Autodesk Fusion 360 part; units mm, degrees
(part 2 of 8)
  spline S22 degree 5 poles (-2.980343, -5.720145) (-2.978626, -5.718892) (-2.975196, -5.716385) (-2.970061, -5.712616) (-2.963235, -5.707577) (-2.954738, -5.701255) (-2.946275, -5.694909) (-2.937848, -5.688539) (-2.929456, -5.682145) (-2.9211, -5.675727) (-2.912779, -5.669285) (-2.904494, -5.662819) (-2.896246, -5.656329) (-2.888035, -5.649814) (-2.87986, -5.643276) (-2.871723, -5.636713) (-2.863622, -5.630126) (-2.85556, -5.623515) (-2.847536, -5.616879) (-2.839549, -5.610219) (-2.831602, -5.603535) (-2.823693, -5.596825) (-2.815824, -5.590091) (-2.807994, -5.583333) (-2.800204, -5.576549) (-2.792454, -5.56974) (-2.784745, -5.562907) (-2.777076, -5.556048) (-2.769449, -5.549164) (-2.761864, -5.542255) (-2.754321, -5.53532) (-2.74682, -5.528359) (-2.739363, -5.521373) (-2.731949, -5.514361) (-2.72458, -5.507322) (-2.717254, -5.500258) (-2.709974, -5.493167) (-2.702738, -5.48605) (-2.695549, -5.478906) (-2.688406, -5.471736) (-2.681311, -5.464538) (-2.674264, -5.457312) (-2.667266, -5.450058) (-2.660318, -5.442777) (-2.653419, -5.435467) (-2.646572, -5.428129) (-2.639774, -5.420762) (-2.633028, -5.413368) (-2.626334, -5.405944) (-2.619694, -5.398491) (-2.613112, -5.391007) (-2.606588, -5.38349) (-2.600125, -5.37594) (-2.593724, -5.368358) (-2.587383, -5.360742) (-2.581101, -5.353096) (-2.574876, -5.34542) (-2.568709, -5.337713) (-2.562604, -5.329974) (-2.556569, -5.322198) (-2.550614, -5.314381) (-2.544748, -5.306517) (-2.540008, -5.300017) (-2.536467, -5.295076) (-2.534085, -5.291717) (-2.532839, -5.289949) (-2.532719, -5.289779) knots -1 -1 -1 -1 -1 -1 -0.98571429 -0.97142857 -0.95714286 -0.94285714 -0.92857143 -0.91428571 -0.9 -0.88571429 -0.87142857 -0.85714286 -0.84285714 -0.82857143 -0.81428571 -0.8 -0.78571429 -0.77142857 -0.75714286 -0.74285714 -0.72857143 -0.71428571 -0.7 -0.68571429 -0.67142857 -0.65714286 -0.64285714 -0.62857143 -0.61428571 -0.6 -0.58571429 -0.57142857 -0.55714286 -0.54285714 -0.52857143 -0.51428571 -0.5 -0.48571429 -0.47142857 -0.45714286 -0.44285714 -0.42857143 -0.41428571 -0.4 -0.38571429 -0.37142857 -0.35714286 -0.34285714 -0.32857143 -0.31428571 -0.3 -0.28571429 -0.27142857 -0.25714286 -0.24285714 -0.22857143 -0.21428571 -0.2 -0.18571429 -0.17142857 -0.15714286 -0.14285714 -0.12857143 -0.1270499 -0.1270499 -0.1270499 -0.1270499 -0.1270499 -0.1270499
  spline S23 degree 3 poles (-2.264018, -5.410236) (-2.259583, -5.391214) (-2.258906, -5.371507) (-2.265143, -5.332944) (-2.271998, -5.314456) (-2.292409, -5.281148) (-2.30577, -5.266646) (-2.337298, -5.243581) (-2.355164, -5.235238) (-2.393089, -5.225869) (-2.412785, -5.224934) (-2.451426, -5.230665) (-2.470003, -5.237276) (-2.495829, -5.25264) (-2.504278, -5.258953) (-2.519715, -5.273244) (-2.526661, -5.281181) (-2.532719, -5.289779) knots 0 0 0 0 0.00585967 0.00585967 0.01171933 0.01171933 0.017579 0.017579 0.02343867 0.02343867 0.02929834 0.02929834 0.035158 0.035158 0.03831344 0.03831344 0.04146887 0.04146887 0.04146887 0.04146887
  spline S24 degree 5 poles (-2.264018, -5.410236) (-2.264065, -5.410438) (-2.264556, -5.412545) (-2.26548, -5.416558) (-2.266812, -5.422489) (-2.268511, -5.430352) (-2.270479, -5.439964) (-2.272353, -5.44961) (-2.274143, -5.459289) (-2.275859, -5.468996) (-2.277509, -5.478727) (-2.279099, -5.488481) (-2.280627, -5.498259) (-2.282093, -5.508059) (-2.283495, -5.517883) (-2.284832, -5.527731) (-2.286103, -5.537602) (-2.287311, -5.547496) (-2.288458, -5.557412) (-2.289546, -5.567348) (-2.290578, -5.577304) (-2.291555, -5.58728) (-2.292477, -5.597274) (-2.293345, -5.607288) (-2.294158, -5.61732) (-2.294918, -5.62737) (-2.295623, -5.637438) (-2.296276, -5.647524) (-2.296877, -5.657628) (-2.297427, -5.667748) (-2.297927, -5.677885) (-2.298376, -5.688038) (-2.298776, -5.698207) (-2.299128, -5.708392) (-2.29943, -5.718592) (-2.299684, -5.728807) (-2.29989, -5.739038) (-2.300049, -5.749283) (-2.300161, -5.759543) (-2.300225, -5.769817) (-2.300244, -5.780105) (-2.300216, -5.790407) (-2.300143, -5.800722) (-2.300025, -5.811051) (-2.299861, -5.821394) (-2.299652, -5.831749) (-2.299399, -5.842117) (-2.299102, -5.852498) (-2.298761, -5.862891) (-2.298376, -5.873297) (-2.297947, -5.883714) (-2.297476, -5.894144) (-2.296961, -5.904585) (-2.296403, -5.915038) (-2.295803, -5.925503) (-2.295161, -5.935978) (-2.294476, -5.946465) (-2.293749, -5.956963) (-2.292981, -5.967472) (-2.292171, -5.977991) (-2.29132, -5.98852) (-2.290427, -5.99906) (-2.289494, -6.00961) (-2.288714, -6.018059) (-2.288111, -6.0244) (-2.287701, -6.028629) (-2.287494, -6.030744) knots 0.1270499 0.1270499 0.1270499 0.1270499 0.1270499 0.1270499 0.12857143 0.14285714 0.15714286 0.17142857 0.18571429 0.2 0.21428571 0.22857143 0.24285714 0.25714286 0.27142857 0.28571429 0.3 0.31428571 0.32857143 0.34285714 0.35714286 0.37142857 0.38571429 0.4 0.41428571 0.42857143 0.44285714 0.45714286 0.47142857 0.48571429 0.5 0.51428571 0.52857143 0.54285714 0.55714286 0.57142857 0.58571429 0.6 0.61428571 0.62857143 0.64285714 0.65714286 0.67142857 0.68571429 0.7 0.71428571 0.72857143 0.74285714 0.75714286 0.77142857 0.78571429 0.8 0.81428571 0.82857143 0.84285714 0.85714286 0.87142857 0.88571429 0.9 0.91428571 0.92857143 0.94285714 0.95714286 0.97142857 0.98571429 1 1 1 1 1 1
  arc A8 (-2.287494, -6.030744) -> (-2.072239, -6.108054) centre (0, 0) ccw
  spline S25 degree 5 poles (-2.072239, -6.108054) (-2.070733, -6.106554) (-2.067726, -6.103552) (-2.063226, -6.099044) (-2.057249, -6.093023) (-2.049817, -6.085477) (-2.042422, -6.077914) (-2.035066, -6.070332) (-2.027749, -6.062732) (-2.02047, -6.055113) (-2.01323, -6.047477) (-2.00603, -6.039822) (-1.998869, -6.032149) (-1.991748, -6.024457) (-1.984667, -6.016748) (-1.977627, -6.00902) (-1.970627, -6.001274) (-1.963669, -5.993509) (-1.956751, -5.985726) (-1.949875, -5.977925) (-1.943041, -5.970106) (-1.936249, -5.962268) (-1.9295, -5.954411) (-1.922793, -5.946537) (-1.91613, -5.938643) (-1.909511, -5.930731) (-1.902935, -5.922801) (-1.896403, -5.914852) (-1.889916, -5.906885) (-1.883475, -5.898898) (-1.877079, -5.890893) (-1.870729, -5.88287) (-1.864425, -5.874827) (-1.858169, -5.866765) (-1.85196, -5.858684) (-1.845799, -5.850584) (-1.839686, -5.842465) (-1.833622, -5.834327) (-1.827607, -5.82617) (-1.821642, -5.817992) (-1.815729, -5.809796) (-1.809868, -5.801579) (-1.804059, -5.793342) (-1.798304, -5.785085) (-1.792602, -5.776808) (-1.786955, -5.76851) (-1.781362, -5.760193) (-1.775823, -5.751855) (-1.770341, -5.743497) (-1.764917, -5.735117) (-1.759554, -5.726716) (-1.754254, -5.718292) (-1.74902, -5.709844) (-1.743851, -5.701373) (-1.738747, -5.692879) (-1.733705, -5.684363) (-1.728725, -5.675827) (-1.723807, -5.667269) (-1.718955, -5.658689) (-1.714178, -5.650083) (-1.709486, -5.641448) (-1.704889, -5.63278) (-1.701196, -5.625633) (-1.698451, -5.62021) (-1.69661, -5.616526) (-1.695649, -5.614589) (-1.695556, -5.614403) knots -1 -1 -1 -1 -1 -1 -0.98571429 -0.97142857 -0.95714286 -0.94285714 -0.92857143 -0.91428571 -0.9 -0.88571429 -0.87142857 -0.85714286 -0.84285714 -0.82857143 -0.81428571 -0.8 -0.78571429 -0.77142857 -0.75714286 -0.74285714 -0.72857143 -0.71428571 -0.7 -0.68571429 -0.67142857 -0.65714286 -0.64285714 -0.62857143 -0.61428571 -0.6 -0.58571429 -0.57142857 -0.55714286 -0.54285714 -0.52857143 -0.51428571 -0.5 -0.48571429 -0.47142857 -0.45714286 -0.44285714 -0.42857143 -0.41428571 -0.4 -0.38571429 -0.37142857 -0.35714286 -0.34285714 -0.32857143 -0.31428571 -0.3 -0.28571429 -0.27142857 -0.25714286 -0.24285714 -0.22857143 -0.21428571 -0.2 -0.18571429 -0.17142857 -0.15714286 -0.14285714 -0.12857143 -0.1270499 -0.1270499 -0.1270499 -0.1270499 -0.1270499 -0.1270499
  spline S26 degree 3 poles (-1.411616, -5.692431) (-1.410137, -5.672955) (-1.412476, -5.653376) (-1.424527, -5.616217) (-1.434124, -5.598992) (-1.45938, -5.56919) (-1.474798, -5.556898) (-1.509477, -5.538916) (-1.528408, -5.533397) (-1.567318, -5.529928) (-1.586925, -5.53201) (-1.62424, -5.543572) (-1.641589, -5.552942) (-1.664767, -5.572068) (-1.672153, -5.579597) (-1.685229, -5.596076) (-1.690881, -5.604981) (-1.695556, -5.614403) knots 0 0 0 0 0.00585967 0.00585967 0.01171933 0.01171933 0.017579 0.017579 0.02343867 0.02343867 0.02929834 0.02929834 0.035158 0.035158 0.03831344 0.03831344 0.04146887 0.04146887 0.04146887 0.04146887
  spline S27 degree 5 poles (-1.411616, -5.692431) (-1.411632, -5.692638) (-1.411795, -5.694795) (-1.412095, -5.698902) (-1.412507, -5.704967) (-1.412985, -5.712997) (-1.413463, -5.722796) (-1.413843, -5.732616) (-1.414134, -5.742455) (-1.414348, -5.75231) (-1.414494, -5.762179) (-1.414576, -5.772062) (-1.414594, -5.781958) (-1.414547, -5.791867) (-1.414433, -5.80179) (-1.41425, -5.811726) (-1.414, -5.821676) (-1.413683, -5.831638) (-1.413303, -5.841613) (-1.412862, -5.851599) (-1.412362, -5.861596) (-1.411804, -5.871604) (-1.41119, -5.881622) (-1.410519, -5.89165) (-1.409792, -5.901689) (-1.409008, -5.911737) (-1.408169, -5.921795) (-1.407274, -5.931863) (-1.406326, -5.94194) (-1.405325, -5.952025) (-1.404271, -5.962119) (-1.403165, -5.972222) (-1.402009, -5.982333) (-1.400801, -5.992452) (-1.399543, -6.002579) (-1.398235, -6.012713) (-1.396877, -6.022855) (-1.39547, -6.033005) (-1.394014, -6.043161) (-1.392509, -6.053325) (-1.390957, -6.063495) (-1.389357, -6.073672) (-1.38771, -6.083856) (-1.386016, -6.094045) (-1.384276, -6.104242) (-1.382489, -6.114444) (-1.380656, -6.124652) (-1.378778, -6.134865) (-1.376854, -6.145085) (-1.374885, -6.15531) (-1.372872, -6.16554) (-1.370813, -6.175775) (-1.368711, -6.186015) (-1.366564, -6.196261) (-1.364374, -6.206511) (-1.36214, -6.216766) (-1.359862, -6.227025) (-1.357541, -6.237289) (-1.355178, -6.247557) (-1.352772, -6.25783) (-1.350323, -6.268106) (-1.347832, -6.278386) (-1.345299, -6.28867) (-1.343239, -6.2969) (-1.341675, -6.303075) (-1.340624, -6.307192) (-1.340096, -6.30925) knots 0.1270499 0.1270499 0.1270499 0.1270499 0.1270499 0.1270499 0.12857143 0.14285714 0.15714286 0.17142857 0.18571429 0.2 0.21428571 0.22857143 0.24285714 0.25714286 0.27142857 0.28571429 0.3 0.31428571 0.32857143 0.34285714 0.35714286 0.37142857 0.38571429 0.4 0.41428571 0.42857143 0.44285714 0.45714286 0.47142857 0.48571429 0.5 0.51428571 0.52857143 0.54285714 0.55714286 0.57142857 0.58571429 0.6 0.61428571 0.62857143 0.64285714 0.65714286 0.67142857 0.68571429 0.7 0.71428571 0.72857143 0.74285714 0.75714286 0.77142857 0.78571429 0.8 0.81428571 0.82857143 0.84285714 0.85714286 0.87142857 0.88571429 0.9 0.91428571 0.92857143 0.94285714 0.95714286 0.97142857 0.98571429 1 1 1 1 1 1
  arc A9 (-1.340096, -6.30925) -> (-1.115563, -6.352796) centre (0, 0) ccw
  spline S28 degree 5 poles (-1.115563, -6.352796) (-1.114304, -6.351084) (-1.11179, -6.347658) (-1.108031, -6.342516) (-1.103044, -6.335653) (-1.09685, -6.327061) (-1.090697, -6.318457) (-1.084584, -6.309841) (-1.078513, -6.301213) (-1.072482, -6.292573) (-1.066493, -6.283921) (-1.060545, -6.275257) (-1.05464, -6.26658) (-1.048776, -6.257892) (-1.042956, -6.249192) (-1.037177, -6.24048) (-1.031442, -6.231756) (-1.02575, -6.22302) (-1.020102, -6.214273) (-1.014497, -6.205513) (-1.008937, -6.196742) (-1.003421, -6.187959) (-0.99795, -6.179165) (-0.992525, -6.170359) (-0.987144, -6.161541) (-0.98181, -6.152711) (-0.976522, -6.14387) (-0.97128, -6.135017) (-0.966086, -6.126153) (-0.960939, -6.117277) (-0.95584, -6.108389) (-0.950789, -6.09949) (-0.945787, -6.090579) (-0.940835, -6.081657) (-0.935932, -6.072723) (-0.931079, -6.063778) (-0.926277, -6.054821) (-0.921527, -6.045852) (-0.916828, -6.036872) (-0.912181, -6.02788) (-0.907588, -6.018877) (-0.90305, -6.009862) (-0.898567, -6.000835) (-0.894139, -5.991796) (-0.889768, -5.982746) (-0.885454, -5.973683) (-0.881195, -5.964609) (-0.876995, -5.955524) (-0.872852, -5.946427) (-0.868771, -5.937318) (-0.864753, -5.928196) (-0.860802, -5.919061) (-0.856918, -5.909913) (-0.853103, -5.900753) (-0.849355, -5.891579) (-0.845673, -5.882394) (-0.842054, -5.873197) (-0.8385, -5.863989) (-0.835015, -5.854768) (-0.831607, -5.845534) (-0.828288, -5.836284) (-0.825068, -5.827017) (-0.82251, -5.81939) (-0.820625, -5.813611) (-0.819368, -5.809689) (-0.818713, -5.807628) (-0.81865, -5.80743) knots -1 -1 -1 -1 -1 -1 -0.98571429 -0.97142857 -0.95714286 -0.94285714 -0.92857143 -0.91428571 -0.9 -0.88571429 -0.87142857 -0.85714286 -0.84285714 -0.82857143 -0.81428571 -0.8 -0.78571429 -0.77142857 -0.75714286 -0.74285714 -0.72857143 -0.71428571 -0.7 -0.68571429 -0.67142857 -0.65714286 -0.64285714 -0.62857143 -0.61428571 -0.6 -0.58571429 -0.57142857 -0.55714286 -0.54285714 -0.52857143 -0.51428571 -0.5 -0.48571429 -0.47142857 -0.45714286 -0.44285714 -0.42857143 -0.41428571 -0.4 -0.38571429 -0.37142857 -0.35714286 -0.34285714 -0.32857143 -0.31428571 -0.3 -0.28571429 -0.27142857 -0.25714286 -0.24285714 -0.22857143 -0.21428571 -0.2 -0.18571429 -0.17142857 -0.15714286 -0.14285714 -0.12857143 -0.1270499 -0.1270499 -0.1270499 -0.1270499 -0.1270499 -0.1270499
  spline S29 degree 3 poles (-0.526127, -5.8412) (-0.527638, -5.821726) (-0.532938, -5.802734) (-0.55052, -5.76785) (-0.562634, -5.752292) (-0.592144, -5.726694) (-0.609257, -5.7169) (-0.646275, -5.704423) (-0.665826, -5.701859) (-0.70481, -5.704369) (-0.72387, -5.70942) (-0.758982, -5.726543) (-0.774698, -5.738451) (-0.794685, -5.760891) (-0.800835, -5.769459) (-0.811241, -5.787741) (-0.815469, -5.797404) (-0.81865, -5.80743) knots 0 0 0 0 0.00585967 0.00585967 0.01171933 0.01171933 0.017579 0.017579 0.02343867 0.02343867 0.02929834 0.02929834 0.035158 0.035158 0.03831344 0.03831344 0.04146887 0.04146887 0.04146887 0.04146887
  spline S30 degree 5 poles (-0.526127, -5.8412) (-0.526111, -5.841408) (-0.525943, -5.843564) (-0.525613, -5.847669) (-0.525094, -5.853725) (-0.524341, -5.861734) (-0.523317, -5.871492) (-0.522193, -5.881255) (-0.52098, -5.891022) (-0.519687, -5.900794) (-0.518325, -5.91057) (-0.516897, -5.920349) (-0.515404, -5.930132) (-0.513845, -5.939918) (-0.512217, -5.949708) (-0.51052, -5.9595) (-0.508754, -5.969294) (-0.50692, -5.979092) (-0.505022, -5.988891) (-0.503061, -5.998693) (-0.501041, -6.008496) (-0.498963, -6.018302) (-0.496826, -6.028109) (-0.494632, -6.037917) (-0.492381, -6.047727) (-0.490073, -6.057538) (-0.487708, -6.06735) (-0.485287, -6.077163) (-0.482812, -6.086977) (-0.480282, -6.096792) (-0.4777, -6.106607) (-0.475065, -6.116422) (-0.472379, -6.126238) (-0.469641, -6.136054) (-0.466851, -6.14587) (-0.464012, -6.155686) (-0.461121, -6.165502) (-0.458181, -6.175318) (-0.455192, -6.185133) (-0.452154, -6.194948) (-0.449067, -6.204762) (-0.445933, -6.214576) (-0.442751, -6.224388) (-0.439521, -6.2342) (-0.436245, -6.244011) (-0.432922, -6.253821) (-0.429552, -6.26363) (-0.426137, -6.273437) (-0.422675, -6.283243) (-0.419169, -6.293047) (-0.415617, -6.30285) (-0.41202, -6.312651) (-0.408379, -6.322451) (-0.404694, -6.332248) (-0.400964, -6.342044) (-0.397191, -6.351838) (-0.393374, -6.361629) (-0.389514, -6.371419) (-0.385611, -6.381206) (-0.381665, -6.39099) (-0.377676, -6.400772) (-0.373645, -6.410552) (-0.369572, -6.420328) (-0.36628, -6.428148) (-0.363791, -6.434011) (-0.362124, -6.437919) (-0.361288, -6.439873) knots 0.1270499 0.1270499 0.1270499 0.1270499 0.1270499 0.1270499 0.12857143 0.14285714 0.15714286 0.17142857 0.18571429 0.2 0.21428571 0.22857143 0.24285714 0.25714286 0.27142857 0.28571429 0.3 0.31428571 0.32857143 0.34285714 0.35714286 0.37142857 0.38571429 0.4 0.41428571 0.42857143 0.44285714 0.45714286 0.47142857 0.48571429 0.5 0.51428571 0.52857143 0.54285714 0.55714286 0.57142857 0.58571429 0.6 0.61428571 0.62857143 0.64285714 0.65714286 0.67142857 0.68571429 0.7 0.71428571 0.72857143 0.74285714 0.75714286 0.77142857 0.78571429 0.8 0.81428571 0.82857143 0.84285714 0.85714286 0.87142857 0.88571429 0.9 0.91428571 0.92857143 0.94285714 0.95714286 0.97142857 0.98571429 1 1 1 1 1 1
  arc A10 (-0.361288, -6.439873) -> (-0.132739, -6.448634) centre (0, 0) ccw
  spline S31 degree 5 poles (-0.132739, -6.448634) (-0.131756, -6.44675) (-0.129795, -6.44298) (-0.126865, -6.437325) (-0.122984, -6.42978) (-0.118174, -6.420344) (-0.113406, -6.410902) (-0.108681, -6.401454) (-0.103997, -6.392) (-0.099356, -6.382541) (-0.094758, -6.373075) (-0.090203, -6.363605) (-0.085691, -6.354129) (-0.081223, -6.344647) (-0.076798, -6.33516) (-0.072417, -6.325669) (-0.068081, -6.316171) (-0.063789, -6.306669) (-0.059542, -6.297162) (-0.055341, -6.28765) (-0.051185, -6.278133) (-0.047074, -6.268611) (-0.04301, -6.259084) (-0.038992, -6.249553) (-0.035021, -6.240017) (-0.031097, -6.230477) (-0.02722, -6.220932) (-0.023391, -6.211383) (-0.019611, -6.201829) (-0.015879, -6.192272) (-0.012196, -6.18271) (-0.008563, -6.173144) (-0.00498, -6.163574) (-0.001448, -6.154) (0.002034, -6.144423) (0.005464, -6.134841) (0.008842, -6.125256) (0.012168, -6.115668) (0.015441, -6.106076) (0.018661, -6.09648) (0.021826, -6.086881) (0.024935, -6.077279) (0.027987, -6.067673) (0.030983, -6.058065) (0.033921, -6.048453) (0.036802, -6.038838) (0.039625, -6.029221) (0.04239, -6.0196) (0.045095, -6.009978) (0.047738, -6.000352) (0.050316, -5.990724) (0.052827, -5.981093) (0.055269, -5.97146) (0.057641, -5.961824) (0.059944, -5.952186) (0.062182, -5.942546) (0.064354, -5.932905) (0.066461, -5.923262) (0.068498, -5.913617) (0.070456, -5.903971) (0.072323, -5.894323) (0.074091, -5.884673) (0.075455, -5.876745) (0.076436, -5.870746) (0.07708, -5.866678) (0.077412, -5.864541) (0.077444, -5.864336) knots -1 -1 -1 -1 -1 -1 -0.98571429 -0.97142857 -0.95714286 -0.94285714 -0.92857143 -0.91428571 -0.9 -0.88571429 -0.87142857 -0.85714286 -0.84285714 -0.82857143 -0.81428571 -0.8 -0.78571429 -0.77142857 -0.75714286 -0.74285714 -0.72857143 -0.71428571 -0.7 -0.68571429 -0.67142857 -0.65714286 -0.64285714 -0.62857143 -0.61428571 -0.6 -0.58571429 -0.57142857 -0.55714286 -0.54285714 -0.52857143 -0.51428571 -0.5 -0.48571429 -0.47142857 -0.45714286 -0.44285714 -0.42857143 -0.41428571 -0.4 -0.38571429 -0.37142857 -0.35714286 -0.34285714 -0.32857143 -0.31428571 -0.3 -0.28571429 -0.27142857 -0.25714286 -0.24285714 -0.22857143 -0.21428571 -0.2 -0.18571429 -0.17142857 -0.15714286 -0.14285714 -0.12857143 -0.1270499 -0.1270499 -0.1270499 -0.1270499 -0.1270499 -0.1270499
  spline S32 degree 3 poles (0.371694, -5.853057) (0.367228, -5.834042) (0.359091, -5.816081) (0.33639, -5.78429) (0.322043, -5.770763) (0.288972, -5.74997) (0.270564, -5.742903) (0.232075, -5.736223) (0.212362, -5.736673) (0.174218, -5.745105) (0.156152, -5.753006) (0.124066, -5.775288) (0.110352, -5.789456) (0.094025, -5.814684) (0.089254, -5.824091) (0.081761, -5.843747) (0.079058, -5.853942) (0.077444, -5.864336) knots 0 0 0 0 0.00585967 0.00585967 0.01171933 0.01171933 0.017579 0.017579 0.02343867 0.02343867 0.02929834 0.02929834 0.035158 0.035158 0.03831344 0.03831344 0.04146887 0.04146887 0.04146887 0.04146887
  spline S33 degree 5 poles (0.371694, -5.853057) (0.371741, -5.853259) (0.372236, -5.855364) (0.373189, -5.859371) (0.374627, -5.865277) (0.376594, -5.873077) (0.379095, -5.882565) (0.381696, -5.892041) (0.384386, -5.901509) (0.387156, -5.910969) (0.389994, -5.920422) (0.392898, -5.929869) (0.395867, -5.93931) (0.398902, -5.948743) (0.402004, -5.958169) (0.405176, -5.967587) (0.408417, -5.976998) (0.411725, -5.9864) (0.415097, -5.995795) (0.41853, -6.005183) (0.422023, -6.014563) (0.425574, -6.023936) (0.429183, -6.033302) (0.432848, -6.042661) (0.436571, -6.052012) (0.44035, -6.061356) (0.444185, -6.070692) (0.448075, -6.08002) (0.452019, -6.089341) (0.456017, -6.098655) (0.460068, -6.107961) (0.46417, -6.117259) (0.468323, -6.126549) (0.472528, -6.135832) (0.476783, -6.145108) (0.481088, -6.154375) (0.485442, -6.163635) (0.489846, -6.172887) (0.494299, -6.182131) (0.498799, -6.191367) (0.503348, -6.200595) (0.507944, -6.209815) (0.512587, -6.219027) (0.517276, -6.228231) (0.522012, -6.237426) (0.526793, -6.246614) (0.531621, -6.255793) (0.536493, -6.264964) (0.541411, -6.274127) (0.546373, -6.283281) (0.551379, -6.292427) (0.55643, -6.301564) (0.561524, -6.310693) (0.566662, -6.319813) (0.571843, -6.328925) (0.577067, -6.338028) (0.582334, -6.347122) (0.587643, -6.356207) (0.592995, -6.365284) (0.598388, -6.374351) (0.603823, -6.38341) (0.6093, -6.392459) (0.614818, -6.4015) (0.619265, -6.408725) (0.622619, -6.41414) (0.624864, -6.417748) (0.625988, -6.419551) knots 0.1270499 0.1270499 0.1270499 0.1270499 0.1270499 0.1270499 0.12857143 0.14285714 0.15714286 0.17142857 0.18571429 0.2 0.21428571 0.22857143 0.24285714 0.25714286 0.27142857 0.28571429 0.3 0.31428571 0.32857143 0.34285714 0.35714286 0.37142857 0.38571429 0.4 0.41428571 0.42857143 0.44285714 0.45714286 0.47142857 0.48571429 0.5 0.51428571 0.52857143 0.54285714 0.55714286 0.57142857 0.58571429 0.6 0.61428571 0.62857143 0.64285714 0.65714286 0.67142857 0.68571429 0.7 0.71428571 0.72857143 0.74285714 0.75714286 0.77142857 0.78571429 0.8 0.81428571 0.82857143 0.84285714 0.85714286 0.87142857 0.88571429 0.9 0.91428571 0.92857143 0.94285714 0.95714286 0.97142857 0.98571429 1 1 1 1 1 1
  arc A11 (0.625988, -6.419551) -> (0.853196, -6.393321) centre (0, 0) ccw
  spline S34 degree 5 poles (0.853196, -6.393321) (0.85388, -6.391309) (0.855243, -6.387284) (0.857275, -6.381248) (0.859959, -6.373199) (0.863272, -6.363139) (0.866542, -6.35308) (0.86977, -6.343022) (0.872956, -6.332964) (0.876098, -6.322907) (0.879198, -6.31285) (0.882254, -6.302795) (0.885267, -6.292742) (0.888235, -6.282689) (0.89116, -6.272638) (0.89404, -6.262589) (0.896876, -6.252541) (0.899667, -6.242495) (0.902413, -6.232451) (0.905113, -6.222409) (0.907768, -6.212369) (0.910377, -6.202331) (0.912939, -6.192296) (0.915455, -6.182263) (0.917924, -6.172233) (0.920346, -6.162205) (0.92272, -6.15218) (0.925046, -6.142159) (0.927324, -6.13214) (0.929553, -6.122125) (0.931733, -6.112113) (0.933863, -6.102105) (0.935943, -6.0921) (0.937973, -6.082099) (0.939952, -6.072102) (0.941879, -6.06211) (0.943755, -6.052121) (0.945578, -6.042137) (0.947349, -6.032158) (0.949065, -6.022183) (0.950728, -6.012214) (0.952335, -6.002249) (0.953885, -5.99229) (0.955379, -5.982337) (0.956816, -5.972389) (0.958195, -5.962448) (0.959517, -5.952512) (0.960781, -5.942582) (0.961985, -5.932659) (0.963128, -5.922743) (0.964206, -5.912834) (0.965217, -5.902933) (0.96616, -5.89304) (0.967033, -5.883155) (0.967839, -5.873278) (0.968578, -5.86341) (0.969253, -5.85355) (0.969863, -5.843698) (0.970404, -5.833856) (0.970867, -5.824024) (0.97124, -5.814204) (0.971514, -5.804397) (0.971652, -5.796353) (0.971705, -5.790275) (0.97172, -5.786157) (0.971723, -5.783994) (0.971723, -5.783786) knots -1 -1 -1 -1 -1 -1 -0.98571429 -0.97142857 -0.95714286 -0.94285714 -0.92857143 -0.91428571 -0.9 -0.88571429 -0.87142857 -0.85714286 -0.84285714 -0.82857143 -0.81428571 -0.8 -0.78571429 -0.77142857 -0.75714286 -0.74285714 -0.72857143 -0.71428571 -0.7 -0.68571429 -0.67142857 -0.65714286 -0.64285714 -0.62857143 -0.61428571 -0.6 -0.58571429 -0.57142857 -0.55714286 -0.54285714 -0.52857143 -0.51428571 -0.5 -0.48571429 -0.47142857 -0.45714286 -0.44285714 -0.42857143 -0.41428571 -0.4 -0.38571429 -0.37142857 -0.35714286 -0.34285714 -0.32857143 -0.31428571 -0.3 -0.28571429 -0.27142857 -0.25714286 -0.24285714 -0.22857143 -0.21428571 -0.2 -0.18571429 -0.17142857 -0.15714286 -0.14285714 -0.12857143 -0.1270499 -0.1270499 -0.1270499 -0.1270499 -0.1270499 -0.1270499
  spline S35 degree 3 poles (1.260803, -5.727723) (1.253486, -5.709612) (1.242703, -5.693104) (1.215415, -5.665151) (1.199171, -5.653973) (1.163314, -5.638472) (1.144043, -5.634297) (1.104985, -5.633571) (1.085572, -5.637025) (1.049163, -5.651181) (1.032514, -5.661747) (1.004205, -5.688666) (0.992815, -5.704761) (0.98053, -5.732186) (0.977252, -5.74221) (0.972846, -5.76278) (0.971731, -5.773268) (0.971723, -5.783786) knots 0 0 0 0 0.00585967 0.00585967 0.01171933 0.01171933 0.017579 0.017579 0.02343867 0.02343867 0.02929834 0.02929834 0.035158 0.035158 0.03831344 0.03831344 0.04146887 0.04146887 0.04146887 0.04146887
  spline S36 degree 5 poles (1.260803, -5.727723) (1.260881, -5.727916) (1.261691, -5.72992) (1.263245, -5.733735) (1.265567, -5.739352) (1.268701, -5.746761) (1.272621, -5.755755) (1.276638, -5.764724) (1.280743, -5.77367) (1.284924, -5.782596) (1.289172, -5.791505) (1.293484, -5.800398) (1.297859, -5.809275) (1.302298, -5.818134) (1.306803, -5.826976) (1.311376, -5.8358) (1.316015, -5.844605) (1.320719, -5.853393) (1.325486, -5.862163) (1.330312, -5.870916) (1.335196, -5.879653) (1.340136, -5.888375) (1.345132, -5.89708) (1.350183, -5.905769) (1.35529, -5.914443) (1.360451, -5.9231) (1.365666, -5.931741) (1.370934, -5.940367) (1.376255, -5.948976) (1.381628, -5.95757) (1.387052, -5.966149) (1.392525, -5.974712) (1.398048, -5.98326) (1.40362, -5.991792) (1.409241, -6.000309) (1.41491, -6.008811) (1.420628, -6.017297) (1.426392, -6.025768) (1.432203, -6.034224) (1.438061, -6.042665) (1.443965, -6.051091) (1.449915, -6.059501) (1.455909, -6.067896) (1.461949, -6.076277) (1.468033, -6.084642) (1.474161, -6.092992) (1.480333, -6.101326) (1.486548, -6.109646) (1.492807, -6.117951) (1.499108, -6.12624) (1.505452, -6.134515) (1.511838, -6.142774) (1.518266, -6.151018) (1.524736, -6.159247) (1.531247, -6.167461) (1.5378, -6.17566) (1.544393, -6.183843) (1.551027, -6.192012) (1.557701, -6.200165) (1.564416, -6.208303) (1.57117, -6.216426) (1.577963, -6.224533) (1.584797, -6.232625) (1.590295, -6.239087) (1.594436, -6.243926) (1.597205, -6.247149) (1.598591, -6.24876) knots 0.1270499 0.1270499 0.1270499 0.1270499 0.1270499 0.1270499 0.12857143 0.14285714 0.15714286 0.17142857 0.18571429 0.2 0.21428571 0.22857143 0.24285714 0.25714286 0.27142857 0.28571429 0.3 0.31428571 0.32857143 0.34285714 0.35714286 0.37142857 0.38571429 0.4 0.41428571 0.42857143 0.44285714 0.45714286 0.47142857 0.48571429 0.5 0.51428571 0.52857143 0.54285714 0.55714286 0.57142857 0.58571429 0.6 0.61428571 0.62857143 0.64285714 0.65714286 0.67142857 0.68571429 0.7 0.71428571 0.72857143 0.74285714 0.75714286 0.77142857 0.78571429 0.8 0.81428571 0.82857143 0.84285714 0.85714286 0.87142857 0.88571429 0.9 0.91428571 0.92857143 0.94285714 0.95714286 0.97142857 0.98571429 1 1 1 1 1 1
  arc A12 (1.598591, -6.24876) -> (1.819133, -6.188155) centre (0, 0) ccw
  spline S37 degree 5 poles (1.819133, -6.188155) (1.819501, -6.186061) (1.820234, -6.181876) (1.821321, -6.1756) (1.822745, -6.167236) (1.824483, -6.156788) (1.82618, -6.146348) (1.827835, -6.135914) (1.829447, -6.125488) (1.831018, -6.115069) (1.832546, -6.104658) (1.834032, -6.094254) (1.835474, -6.083858) (1.836874, -6.07347) (1.83823, -6.063091) (1.839542, -6.052719) (1.840811, -6.042356) (1.842035, -6.032002) (1.843216, -6.021657) (1.844352, -6.01132) (1.845443, -6.000992) (1.846489, -5.990674) (1.847489, -5.980365) (1.848444, -5.970066) (1.849353, -5.959776) (1.850216, -5.949496) (1.851032, -5.939227) (1.851801, -5.928968) (1.852523, -5.918719) (1.853197, -5.90848) (1.853823, -5.898253) (1.854401, -5.888037) (1.854929, -5.877832) (1.855408, -5.867639) (1.855838, -5.857457) (1.856217, -5.847287) (1.856546, -5.837129) (1.856824, -5.826984) (1.857051, -5.816851) (1.857225, -5.806732) (1.857346, -5.796625) (1.857413, -5.786532) (1.857425, -5.776453) (1.857382, -5.766389) (1.857283, -5.756338) (1.857129, -5.746303) (1.856919, -5.736281) (1.856652, -5.726275) (1.856327, -5.716285) (1.855943, -5.706311) (1.855496, -5.696353) (1.854984, -5.686414) (1.854405, -5.676493) (1.853759, -5.66659) (1.853048, -5.656706) (1.852272, -5.64684) (1.851434, -5.636993) (1.850533, -5.627164) (1.849566, -5.617354) (1.848522, -5.607567) (1.847392, -5.597805) (1.846165, -5.588071) (1.845073, -5.580101) (1.844199, -5.574086) (1.843585, -5.570013) (1.843257, -5.567876) (1.843226, -5.56767) knots -1 -1 -1 -1 -1 -1 -0.98571429 -0.97142857 -0.95714286 -0.94285714 -0.92857143 -0.91428571 -0.9 -0.88571429 -0.87142857 -0.85714286 -0.84285714 -0.82857143 -0.81428571 -0.8 -0.78571429 -0.77142857 -0.75714286 -0.74285714 -0.72857143 -0.71428571 -0.7 -0.68571429 -0.67142857 -0.65714286 -0.64285714 -0.62857143 -0.61428571 -0.6 -0.58571429 -0.57142857 -0.55714286 -0.54285714 -0.52857143 -0.51428571 -0.5 -0.48571429 -0.47142857 -0.45714286 -0.44285714 -0.42857143 -0.41428571 -0.4 -0.38571429 -0.37142857 -0.35714286 -0.34285714 -0.32857143 -0.31428571 -0.3 -0.28571429 -0.27142857 -0.25714286 -0.24285714 -0.22857143 -0.21428571 -0.2 -0.18571429 -0.17142857 -0.15714286 -0.14285714 -0.12857143 -0.1270499 -0.1270499 -0.1270499 -0.1270499 -0.1270499 -0.1270499
  spline S38 degree 3 poles (2.120359, -5.468135) (2.110364, -5.451354) (2.097187, -5.436686) (2.065952, -5.413225) (2.048193, -5.404658) (2.010389, -5.394812) (1.990707, -5.393629) (1.951996, -5.398872) (1.933337, -5.40525) (1.899516, -5.424797) (1.884675, -5.437781) (1.860807, -5.468706) (1.852007, -5.486351) (1.844053, -5.51533) (1.842343, -5.525737) (1.841129, -5.546738) (1.841628, -5.557274) (1.843226, -5.56767) knots 0 0 0 0 0.00585967 0.00585967 0.01171933 0.01171933 0.017579 0.017579 0.02343867 0.02343867 0.02929834 0.02929834 0.035158 0.035158 0.03831344 0.03831344 0.04146887 0.04146887 0.04146887 0.04146887
  spline S39 degree 5 poles (2.120359, -5.468135) (2.120466, -5.468314) (2.121573, -5.470172) (2.12369, -5.473704) (2.126843, -5.478901) (2.131072, -5.485745) (2.136318, -5.494035) (2.141658, -5.502286) (2.147079, -5.5105) (2.152574, -5.518684) (2.158133, -5.52684) (2.163752, -5.534971) (2.16943, -5.543075) (2.17517, -5.551153) (2.180972, -5.559204) (2.186838, -5.567226) (2.192767, -5.57522) (2.198757, -5.583186) (2.204807, -5.591126) (2.210913, -5.59904) (2.217073, -5.606929) (2.223287, -5.614794) (2.229553, -5.622635) (2.235871, -5.630452) (2.242242, -5.638244) (2.248664, -5.646012) (2.255137, -5.653756) (2.26166, -5.661476) (2.268233, -5.669172) (2.274855, -5.676846) (2.281524, -5.684496) (2.288241, -5.692123) (2.295004, -5.699727) (2.301813, -5.707309) (2.308668, -5.714868) (2.315569, -5.722405) (2.322515, -5.729919) (2.329505, -5.737411) (2.336539, -5.744881) (2.343616, -5.752329) (2.350737, -5.759754) (2.357901, -5.767158) (2.365107, -5.77454) (2.372355, -5.7819) (2.379644, -5.789238) (2.386975, -5.796555) (2.394347, -5.80385) (2.40176, -5.811123) (2.409212, -5.818375) (2.416705, -5.825606) (2.424238, -5.832815) (2.43181, -5.840002) (2.439421, -5.847169) (2.447072, -5.854314) (2.45476, -5.861437) (2.462488, -5.86854) (2.470253, -5.875621) (2.478056, -5.882681) (2.485896, -5.88972) (2.493774, -5.896737) (2.501689, -5.903734) (2.509641, -5.910709) (2.517629, -5.917664) (2.52405, -5.92321) (2.528881, -5.927361) (2.532109, -5.930123) (2.533725, -5.931504) knots 0.1270499 0.1270499 0.1270499 0.1270499 0.1270499 0.1270499 0.12857143 0.14285714 0.15714286 0.17142857 0.18571429 0.2 0.21428571 0.22857143 0.24285714 0.25714286 0.27142857 0.28571429 0.3 0.31428571 0.32857143 0.34285714 0.35714286 0.37142857 0.38571429 0.4 0.41428571 0.42857143 0.44285714 0.45714286 0.47142857 0.48571429 0.5 0.51428571 0.52857143 0.54285714 0.55714286 0.57142857 0.58571429 0.6 0.61428571 0.62857143 0.64285714 0.65714286 0.67142857 0.68571429 0.7 0.71428571 0.72857143 0.74285714 0.75714286 0.77142857 0.78571429 0.8 0.81428571 0.82857143 0.84285714 0.85714286 0.87142857 0.88571429 0.9 0.91428571 0.92857143 0.94285714 0.95714286 0.97142857 0.98571429 1 1 1 1 1 1
  arc A13 (2.533725, -5.931504) -> (2.742431, -5.837943) centre (0, 0) ccw
  spline S40 degree 5 poles (2.742431, -5.837943) (2.742475, -5.835818) (2.742561, -5.83157) (2.742677, -5.825201) (2.742807, -5.816718) (2.74293, -5.806127) (2.743013, -5.79555) (2.743056, -5.784986) (2.743058, -5.774436) (2.74302, -5.763899) (2.742941, -5.753377) (2.742821, -5.742868) (2.74266, -5.732374) (2.742457, -5.721894) (2.742213, -5.711429) (2.741927, -5.700979) (2.741599, -5.690544) (2.741228, -5.680124) (2.740816, -5.66972) (2.74036, -5.659331) (2.739862, -5.648958) (2.739321, -5.638601) (2.738736, -5.62826) (2.738107, -5.617935) (2.737435, -5.607628) (2.736718, -5.597337) (2.735957, -5.587063) (2.735151, -5.576806) (2.7343, -5.566567) (2.733404, -5.556346) (2.732461, -5.546143) (2.731472, -5.535959) (2.730437, -5.525793) (2.729355, -5.515646) (2.728225, -5.505518) (2.727047, -5.495409) (2.725822, -5.48532) (2.724548, -5.475251) (2.723225, -5.465203) (2.721852, -5.455175) (2.720429, -5.445169) (2.718955, -5.435184) (2.717428, -5.425221) (2.715849, -5.415281) (2.714218, -5.405364) (2.712533, -5.395469) (2.710796, -5.385597) (2.709004, -5.375749) (2.707159, -5.365925) (2.705256, -5.356127) (2.703294, -5.346354) (2.701271, -5.336609) (2.699185, -5.326893) (2.697035, -5.317205) (2.694823, -5.307546) (2.69255, -5.297914) (2.690219, -5.28831) (2.687828, -5.278733) (2.685375, -5.269187) (2.682849, -5.259673) (2.680242, -5.250198) (2.677544, -5.240765) (2.675248, -5.233055) (2.673466, -5.227244) (2.672237, -5.223313) (2.671587, -5.221251) (2.671525, -5.221052) knots -1 -1 -1 -1 -1 -1 -0.98571429 -0.97142857 -0.95714286 -0.94285714 -0.92857143 -0.91428571 -0.9 -0.88571429 -0.87142857 -0.85714286 -0.84285714 -0.82857143 -0.81428571 -0.8 -0.78571429 -0.77142857 -0.75714286 -0.74285714 -0.72857143 -0.71428571 -0.7 -0.68571429 -0.67142857 -0.65714286 -0.64285714 -0.62857143 -0.61428571 -0.6 -0.58571429 -0.57142857 -0.55714286 -0.54285714 -0.52857143 -0.51428571 -0.5 -0.48571429 -0.47142857 -0.45714286 -0.44285714 -0.42857143 -0.41428571 -0.4 -0.38571429 -0.37142857 -0.35714286 -0.34285714 -0.32857143 -0.31428571 -0.3 -0.28571429 -0.27142857 -0.25714286 -0.24285714 -0.22857143 -0.21428571 -0.2 -0.18571429 -0.17142857 -0.15714286 -0.14285714 -0.12857143 -0.1270499 -0.1270499 -0.1270499 -0.1270499 -0.1270499 -0.1270499
  spline S41 degree 3 poles (2.930217, -5.08038) (2.917777, -5.065321) (2.902515, -5.052836) (2.868065, -5.034418) (2.849206, -5.028662) (2.810342, -5.024703) (2.79071, -5.026538) (2.753253, -5.037629) (2.735787, -5.04678) (2.705345, -5.071261) (2.692661, -5.086358) (2.673793, -5.120564) (2.66779, -5.139346) (2.664352, -5.169199) (2.664251, -5.179746) (2.666258, -5.200686) (2.668359, -5.211022) (2.671525, -5.221052) knots 0 0 0 0 0.00585967 0.00585967 0.01171933 0.01171933 0.017579 0.017579 0.02343867 0.02343867 0.02929834 0.02929834 0.035158 0.035158 0.03831344 0.03831344 0.04146887 0.04146887 0.04146887 0.04146887
  spline S42 degree 5 poles (2.930217, -5.08038) (2.930349, -5.08054) (2.931727, -5.082207) (2.934359, -5.085375) (2.938267, -5.09003) (2.943491, -5.096148) (2.949942, -5.10354) (2.956478, -5.110879) (2.963091, -5.118169) (2.96977, -5.125418) (2.976508, -5.13263) (2.983303, -5.139808) (2.990152, -5.146951) (2.997057, -5.154058) (3.00402, -5.161129) (3.011042, -5.168161) (3.018122, -5.175157) (3.025258, -5.182115) (3.032449, -5.189038) (3.039691, -5.195928) (3.046984, -5.202784) (3.054325, -5.209608) (3.061715, -5.216401) (3.069152, -5.223161) (3.076637, -5.22989) (3.08417, -5.236586) (3.091749, -5.243251) (3.099375, -5.249885) (3.107046, -5.256488) (3.114761, -5.26306) (3.12252, -5.269603) (3.130322, -5.276115) (3.138167, -5.282598) (3.146054, -5.289052) (3.153982, -5.295476) (3.161952, -5.301871) (3.169964, -5.308237) (3.178016, -5.314574) (3.186107, -5.320882) (3.194239, -5.327162) (3.20241, -5.333414) (3.21062, -5.339637) (3.218868, -5.345833) (3.227154, -5.352) (3.235479, -5.35814) (3.243841, -5.364252) (3.25224, -5.370336) (3.260676, -5.376392) (3.269148, -5.382422) (3.277657, -5.388424) (3.286202, -5.394398) (3.294782, -5.400346) (3.303398, -5.406266) (3.31205, -5.41216) (3.320736, -5.418026) (3.329457, -5.423866) (3.338212, -5.429679) (3.347001, -5.435465) (3.355824, -5.441224) (3.364681, -5.446957) (3.373571, -5.452664) (3.382495, -5.458343) (3.391451, -5.463997) (3.398643, -5.468498) (3.404051, -5.471863) (3.407663, -5.4741) (3.409471, -5.475218) knots 0.1270499 0.1270499 0.1270499 0.1270499 0.1270499 0.1270499 0.12857143 0.14285714 0.15714286 0.17142857 0.18571429 0.2 0.21428571 0.22857143 0.24285714 0.25714286 0.27142857 0.28571429 0.3 0.31428571 0.32857143 0.34285714 0.35714286 0.37142857 0.38571429 0.4 0.41428571 0.42857143 0.44285714 0.45714286 0.47142857 0.48571429 0.5 0.51428571 0.52857143 0.54285714 0.55714286 0.57142857 0.58571429 0.6 0.61428571 0.62857143 0.64285714 0.65714286 0.67142857 0.68571429 0.7 0.71428571 0.72857143 0.74285714 0.75714286 0.77142857 0.78571429 0.8 0.81428571 0.82857143 0.84285714 0.85714286 0.87142857 0.88571429 0.9 0.91428571 0.92857143 0.94285714 0.95714286 0.97142857 0.98571429 1 1 1 1 1 1
  arc A14 (3.409471, -5.475218) -> (3.601448, -5.350894) centre (0, 0) ccw
  spline S43 degree 5 poles (3.601448, -5.350894) (3.601168, -5.348788) (3.600604, -5.344576) (3.599746, -5.338265) (3.59858, -5.329861) (3.597086, -5.319376) (3.595553, -5.30891) (3.593983, -5.298463) (3.592375, -5.288036) (3.590728, -5.277629) (3.589044, -5.267242) (3.587321, -5.256875) (3.58556, -5.246528) (3.58376, -5.236202) (3.581921, -5.225897) (3.580043, -5.215613) (3.578126, -5.20535) (3.576169, -5.195109) (3.574173, -5.18489) (3.572137, -5.174692) (3.570062, -5.164516) (3.567945, -5.154363) (3.565789, -5.144233) (3.563592, -5.134125) (3.561354, -5.124041) (3.559075, -5.11398) (3.556754, -5.103943) (3.554392, -5.09393) (3.551988, -5.083941) (3.549542, -5.073976) (3.547053, -5.064037) (3.544521, -5.054122) (3.541946, -5.044233) (3.539327, -5.03437) (3.536665, -5.024534) (3.533958, -5.014723) (3.531207, -5.00494) (3.528411, -4.995184) (3.525569, -4.985455) (3.522682, -4.975754) (3.519748, -4.966082) (3.516767, -4.956439) (3.513737, -4.946827) (3.510659, -4.937244) (3.507533, -4.927692) (3.504358, -4.91817) (3.501134, -4.908679) (3.49786, -4.89922) (3.494537, -4.889793) (3.491161, -4.8804) (3.48773, -4.871041) (3.484243, -4.861719) (3.480698, -4.852435) (3.477094, -4.843189) (3.473434, -4.833981) (3.469718, -4.824809) (3.465948, -4.815673) (3.462123, -4.806574) (3.458241, -4.797513) (3.454293, -4.788497) (3.45027, -4.779531) (3.446163, -4.770621) (3.442718, -4.763351) (3.440069, -4.75788) (3.438255, -4.754183) (3.437297, -4.752244) (3.437205, -4.752057) knots -1 -1 -1 -1 -1 -1 -0.98571429 -0.97142857 -0.95714286 -0.94285714 -0.92857143 -0.91428571 -0.9 -0.88571429 -0.87142857 -0.85714286 -0.84285714 -0.82857143 -0.81428571 -0.8 -0.78571429 -0.77142857 -0.75714286 -0.74285714 -0.72857143 -0.71428571 -0.7 -0.68571429 -0.67142857 -0.65714286 -0.64285714 -0.62857143 -0.61428571 -0.6 -0.58571429 -0.57142857 -0.55714286 -0.54285714 -0.52857143 -0.51428571 -0.5 -0.48571429 -0.47142857 -0.45714286 -0.44285714 -0.42857143 -0.41428571 -0.4 -0.38571429 -0.37142857 -0.35714286 -0.34285714 -0.32857143 -0.31428571 -0.3 -0.28571429 -0.27142857 -0.25714286 -0.24285714 -0.22857143 -0.21428571 -0.2 -0.18571429 -0.17142857 -0.15714286 -0.14285714 -0.12857143 -0.1270499 -0.1270499 -0.1270499 -0.1270499 -0.1270499 -0.1270499
  spline S44 degree 3 poles (3.671392, -4.573544) (3.6568, -4.560561) (3.639811, -4.550552) (3.602953, -4.537609) (3.583436, -4.534799) (3.544424, -4.536819) (3.525301, -4.541629) (3.489977, -4.558308) (3.474112, -4.570018) (3.447764, -4.598859) (3.437533, -4.615715) (3.424108, -4.6524) (3.421042, -4.671879) (3.422202, -4.701907) (3.423712, -4.712345) (3.428891, -4.732734) (3.432546, -4.742628) (3.437205, -4.752057) knots 0 0 0 0 0.00585967 0.00585967 0.01171933 0.01171933 0.017579 0.017579 0.02343867 0.02343867 0.02929834 0.02929834 0.035158 0.035158 0.03831344 0.03831344 0.04146887 0.04146887 0.04146887 0.04146887
  spline S45 degree 5 poles (3.671392, -4.573544) (3.671548, -4.573683) (3.673164, -4.57512) (3.676248, -4.577849) (3.680822, -4.581853) (3.686918, -4.587101) (3.694422, -4.593422) (3.702001, -4.599677) (3.709649, -4.605873) (3.717357, -4.612017) (3.725117, -4.618116) (3.732928, -4.624172) (3.740787, -4.630186) (3.748696, -4.636156) (3.756657, -4.642081) (3.76467, -4.647959) (3.772735, -4.653792) (3.780849, -4.65958) (3.789013, -4.665324) (3.797222, -4.671027) (3.805476, -4.67669) (3.813773, -4.682313) (3.822113, -4.687898) (3.830495, -4.693444) (3.838919, -4.698951) (3.847386, -4.704419) (3.855894, -4.709849) (3.864443, -4.715241) (3.873032, -4.720596) (3.88166, -4.725914) (3.890326, -4.731195) (3.899031, -4.73644) (3.907774, -4.74165) (3.916553, -4.746824) (3.92537, -4.751962) (3.934223, -4.757066) (3.943112, -4.762134) (3.952036, -4.767168) (3.960997, -4.772167) (3.969991, -4.777132) (3.979021, -4.782063) (3.988084, -4.78696) (3.997182, -4.791824) (4.006313, -4.796654) (4.015477, -4.801451) (4.024673, -4.806215) (4.033903, -4.810946) (4.043164, -4.815644) (4.052458, -4.820309) (4.061783, -4.824942) (4.07114, -4.829542) (4.080528, -4.83411) (4.089947, -4.838646) (4.099396, -4.843149) (4.108876, -4.847621) (4.118386, -4.852061) (4.127926, -4.85647) (4.137496, -4.860846) (4.147094, -4.865191) (4.156723, -4.869505) (4.16638, -4.873787) (4.176065, -4.878038) (4.18578, -4.882258) (4.193574, -4.885609) (4.199433, -4.888109) (4.203344, -4.889769) (4.205301, -4.890597) knots 0.1270499 0.1270499 0.1270499 0.1270499 0.1270499 0.1270499 0.12857143 0.14285714 0.15714286 0.17142857 0.18571429 0.2 0.21428571 0.22857143 0.24285714 0.25714286 0.27142857 0.28571429 0.3 0.31428571 0.32857143 0.34285714 0.35714286 0.37142857 0.38571429 0.4 0.41428571 0.42857143 0.44285714 0.45714286 0.47142857 0.48571429 0.5 0.51428571 0.52857143 0.54285714 0.55714286 0.57142857 0.58571429 0.6 0.61428571 0.62857143 0.64285714 0.65714286 0.67142857 0.68571429 0.7 0.71428571 0.72857143 0.74285714 0.75714286 0.77142857 0.78571429 0.8 0.81428571 0.82857143 0.84285714 0.85714286 0.87142857 0.88571429 0.9 0.91428571 0.92857143 0.94285714 0.95714286 0.97142857 0.98571429 1 1 1 1 1 1
  arc A15 (4.205301, -4.890597) -> (4.376051, -4.738426) centre (0, 0) ccw
  spline S46 degree 5 poles (4.376051, -4.738426) (4.375452, -4.736386) (4.374252, -4.73231) (4.372441, -4.726204) (4.370006, -4.718077) (4.366928, -4.707942) (4.363816, -4.697833) (4.360669, -4.687748) (4.357488, -4.677689) (4.354273, -4.667655) (4.351022, -4.657647) (4.347737, -4.647664) (4.344417, -4.637708) (4.341062, -4.627778) (4.337672, -4.617874) (4.334246, -4.607997) (4.330785, -4.598147) (4.327288, -4.588325) (4.323755, -4.57853) (4.320186, -4.568762) (4.316582, -4.559023) (4.312941, -4.549312) (4.309263, -4.53963) (4.305549, -4.529976) (4.301797, -4.520351) (4.298009, -4.510756) (4.294184, -4.501191) (4.290321, -4.491656) (4.28642, -4.482151) (4.282481, -4.472676) (4.278504, -4.463233) (4.274489, -4.453821) (4.270434, -4.444442) (4.266341, -4.435094) (4.262208, -4.425779) (4.258035, -4.416497) (4.253823, -4.407248) (4.24957, -4.398033) (4.245277, -4.388852) (4.240943, -4.379705) (4.236567, -4.370595) (4.232149, -4.36152) (4.227687, -4.352482) (4.223183, -4.343482) (4.218635, -4.334519) (4.214043, -4.325594) (4.209408, -4.316706) (4.204729, -4.307858) (4.200006, -4.299048) (4.195235, -4.29028) (4.190416, -4.281555) (4.185547, -4.272875) (4.180626, -4.264241) (4.175654, -4.255653) (4.17063, -4.247111) (4.165558, -4.238614) (4.160437, -4.230161) (4.155269, -4.221752) (4.150049, -4.213391) (4.14477, -4.205083) (4.139426, -4.196836) (4.134007, -4.188657) (4.129493, -4.181998) (4.12604, -4.176996) (4.123683, -4.173619) (4.12244, -4.171849) (4.122321, -4.171678) knots -1 -1 -1 -1 -1 -1 -0.98571429 -0.97142857 -0.95714286 -0.94285714 -0.92857143 -0.91428571 -0.9 -0.88571429 -0.87142857 -0.85714286 -0.84285714 -0.82857143 -0.81428571 -0.8 -0.78571429 -0.77142857 -0.75714286 -0.74285714 -0.72857143 -0.71428571 -0.7 -0.68571429 -0.67142857 -0.65714286 -0.64285714 -0.62857143 -0.61428571 -0.6 -0.58571429 -0.57142857 -0.55714286 -0.54285714 -0.52857143 -0.51428571 -0.5 -0.48571429 -0.47142857 -0.45714286 -0.44285714 -0.42857143 -0.41428571 -0.4 -0.38571429 -0.37142857 -0.35714286 -0.34285714 -0.32857143 -0.31428571 -0.3 -0.28571429 -0.27142857 -0.25714286 -0.24285714 -0.22857143 -0.21428571 -0.2 -0.18571429 -0.17142857 -0.15714286 -0.14285714 -0.12857143 -0.1270499 -0.1270499 -0.1270499 -0.1270499 -0.1270499 -0.1270499
  spline S47 degree 3 poles (4.326513, -3.959509) (4.31011, -3.948905) (4.291792, -3.941607) (4.25339, -3.934442) (4.233673, -3.934644) (4.195427, -3.942595) (4.177263, -3.950268) (4.144898, -3.972144) (4.131007, -3.986138) (4.109371, -4.018664) (4.101832, -4.036884) (4.094164, -4.075189) (4.094108, -4.094907) (4.099838, -4.124406) (4.102924, -4.134491) (4.111154, -4.15385) (4.116277, -4.16307) (4.122321, -4.171678) knots 0 0 0 0 0.00585967 0.00585967 0.01171933 0.01171933 0.017579 0.017579 0.02343867 0.02343867 0.02929834 0.02929834 0.035158 0.035158 0.03831344 0.03831344 0.04146887 0.04146887 0.04146887 0.04146887
  spline S48 degree 5 poles (4.326513, -3.959509) (4.326688, -3.959622) (4.328504, -3.960796) (4.331969, -3.963022) (4.3371, -3.96628) (4.343927, -3.970537) (4.352307, -3.975638) (4.360753, -3.980663) (4.369257, -3.985619) (4.377812, -3.990515) (4.386413, -3.995358) (4.395056, -4.00015) (4.403741, -4.004894) (4.412469, -4.009586) (4.421241, -4.014227) (4.430057, -4.018813) (4.438918, -4.023346) (4.447821, -4.027827) (4.456765, -4.032258) (4.465749, -4.036641) (4.47477, -4.040978) (4.483829, -4.045269) (4.492923, -4.049515) (4.502054, -4.053716) (4.51122, -4.057873) (4.520422, -4.061985) (4.52966, -4.066052) (4.538931, -4.070076) (4.548237, -4.074057) (4.557576, -4.077995) (4.566947, -4.081892) (4.57635, -4.085747) (4.585786, -4.089561) (4.595252, -4.093334) (4.60475, -4.097066) (4.614278, -4.100759) (4.623836, -4.104411) (4.633425, -4.108023) (4.643043, -4.111596) (4.652691, -4.11513) (4.662367, -4.118625) (4.672072, -4.122081) (4.681805, -4.125499) (4.691566, -4.128879) (4.701355, -4.132221) (4.711171, -4.135525) (4.721015, -4.138791) (4.730885, -4.14202) (4.740782, -4.145212) (4.750705, -4.148367) (4.760654, -4.151485) (4.770629, -4.154566) (4.78063, -4.157611) (4.790656, -4.16062) (4.800708, -4.163592) (4.810784, -4.166529) (4.820885, -4.169429) (4.831011, -4.172294) (4.84116, -4.175122) (4.851334, -4.177916) (4.861532, -4.180674) (4.871753, -4.183397) (4.881997, -4.186084) (4.890212, -4.188206) (4.896384, -4.189782) (4.900503, -4.190825) (4.902563, -4.191345) knots 0.1270499 0.1270499 0.1270499 0.1270499 0.1270499 0.1270499 0.12857143 0.14285714 0.15714286 0.17142857 0.18571429 0.2 0.21428571 0.22857143 0.24285714 0.25714286 0.27142857 0.28571429 0.3 0.31428571 0.32857143 0.34285714 0.35714286 0.37142857 0.38571429 0.4 0.41428571 0.42857143 0.44285714 0.45714286 0.47142857 0.48571429 0.5 0.51428571 0.52857143 0.54285714 0.55714286 0.57142857 0.58571429 0.6 0.61428571 0.62857143 0.64285714 0.65714286 0.67142857 0.68571429 0.7 0.71428571 0.72857143 0.74285714 0.75714286 0.77142857 0.78571429 0.8 0.81428571 0.82857143 0.84285714 0.85714286 0.87142857 0.88571429 0.9 0.91428571 0.92857143 0.94285714 0.95714286 0.97142857 0.98571429 1 1 1 1 1 1
  arc A16 (4.902563, -4.191345) -> (5.048083, -4.014892) centre (0, 0) ccw
  spline S49 degree 5 poles (5.048083, -4.014892) (5.04718, -4.012968) (5.045371, -4.009123) (5.04265, -4.003365) (5.039002, -3.995704) (5.034414, -3.986159) (5.029795, -3.976643) (5.025146, -3.967157) (5.020466, -3.957701) (5.015757, -3.948276) (5.011017, -3.938881) (5.006246, -3.929517) (5.001445, -3.920184) (4.996614, -3.910882) (4.991751, -3.901612) (4.986858, -3.892374) (4.981934, -3.883168) (4.976978, -3.873994) (4.971992, -3.864853) (4.966974, -3.855745) (4.961925, -3.84667) (4.956844, -3.837629) (4.951731, -3.828621) (4.946587, -3.819648) (4.941411, -3.810709) (4.936202, -3.801804) (4.930961, -3.792935) (4.925688, -3.784101) (4.920382, -3.775303) (4.915043, -3.766541) (4.909671, -3.757815) (4.904266, -3.749127) (4.898827, -3.740476) (4.893355, -3.731863) (4.887849, -3.723288) (4.882308, -3.714751) (4.876733, -3.706254) (4.871124, -3.697796) (4.865479, -3.689378) (4.8598, -3.681) (4.854084, -3.672664) (4.848333, -3.66437) (4.842544, -3.65612) (4.836718, -3.647912) (4.830855, -3.639749) (4.824955, -3.631629) (4.819018, -3.623553) (4.813043, -3.615522) (4.80703, -3.607538) (4.800977, -3.5996) (4.794883, -3.591713) (4.788746, -3.583878) (4.782565, -3.576096) (4.776339, -3.568368) (4.770071, -3.560693) (4.76376, -3.55307) (4.75741, -3.545497) (4.751018, -3.537976) (4.744583, -3.53051) (4.738098, -3.523105) (4.731558, -3.51577) (4.724954, -3.508514) (4.719476, -3.502623) (4.7153, -3.498206) (4.712455, -3.495228) (4.710957, -3.493669) (4.710813, -3.493519) knots -1 -1 -1 -1 -1 -1 -0.98571429 -0.97142857 -0.95714286 -0.94285714 -0.92857143 -0.91428571 -0.9 -0.88571429 -0.87142857 -0.85714286 -0.84285714 -0.82857143 -0.81428571 -0.8 -0.78571429 -0.77142857 -0.75714286 -0.74285714 -0.72857143 -0.71428571 -0.7 -0.68571429 -0.67142857 -0.65714286 -0.64285714 -0.62857143 -0.61428571 -0.6 -0.58571429 -0.57142857 -0.55714286 -0.54285714 -0.52857143 -0.51428571 -0.5 -0.48571429 -0.47142857 -0.45714286 -0.44285714 -0.42857143 -0.41428571 -0.4 -0.38571429 -0.37142857 -0.35714286 -0.34285714 -0.32857143 -0.31428571 -0.3 -0.28571429 -0.27142857 -0.25714286 -0.24285714 -0.22857143 -0.21428571 -0.2 -0.18571429 -0.17142857 -0.15714286 -0.14285714 -0.12857143 -0.1270499 -0.1270499 -0.1270499 -0.1270499 -0.1270499 -0.1270499
  spline S50 degree 3 poles (4.880225, -3.252666) (4.862395, -3.244691) (4.843178, -3.240274) (4.804132, -3.239055) (4.784677, -3.242265) (4.748092, -3.255961) (4.731312, -3.266316) (4.702667, -3.292877) (4.691074, -3.308827) (4.674657, -3.344274) (4.669988, -3.363432) (4.668257, -3.402458) (4.671211, -3.421953) (4.681377, -3.450232) (4.685966, -3.459728) (4.697056, -3.477604) (4.703525, -3.485934) (4.710813, -3.493519) knots 0 0 0 0 0.00585967 0.00585967 0.01171933 0.01171933 0.017579 0.017579 0.02343867 0.02343867 0.02929834 0.02929834 0.035158 0.035158 0.03831344 0.03831344 0.04146887 0.04146887 0.04146887 0.04146887